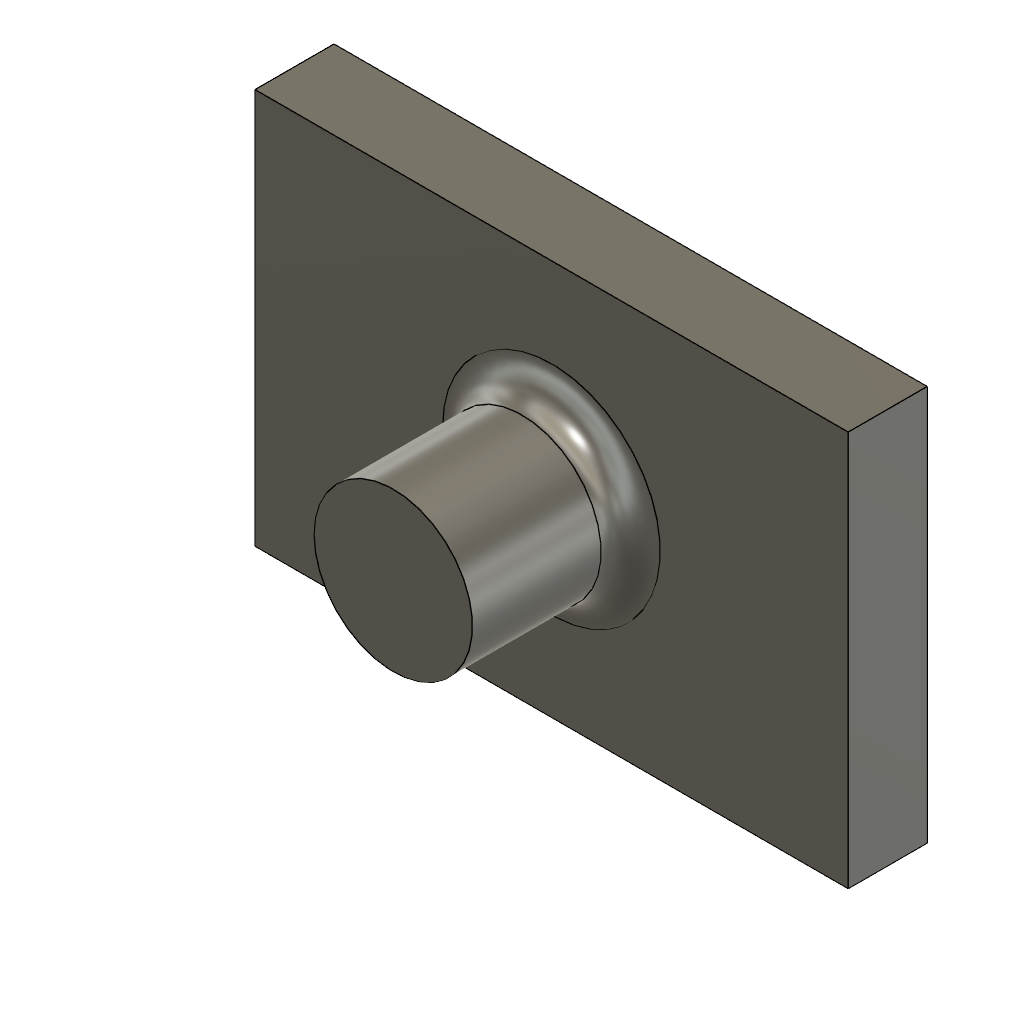
fillet_concave_boss_round (Autodesk Fusion 360 design; units mm, degrees)
part number: 2026-11-12-22-55-53-728
Autodesk Fusion 360 part; units mm, degrees
sketch "Sketch1" plane through (0, 0, 0) normal (0, 0, 1) x (1, 0, 0)
  line L0 (0, 0) -> (30, 0)
  line L1 (30, 0) -> (30, 20)
  line L2 (30, 20) -> (0, 20)
  line L3 (0, 20) -> (0, 0)
extrude "Extrude1" add sketch "Sketch1" along normal blind 4
ref_plane "WorkPlane1" through (0, 0, 4) normal (0, 0, 1) x (1, 0, 0)
sketch "Sketch2" plane through (0, 0, 4) normal (0, 0, 1) x (1, 0, 0)
  circle A0 centre (15, 10) radius 4
extrude "Extrude2" add sketch "Sketch2" along normal blind 8
fillet "Fillet1" radius 1.5 1 edges at (11.2707, 11.4465, 4)
